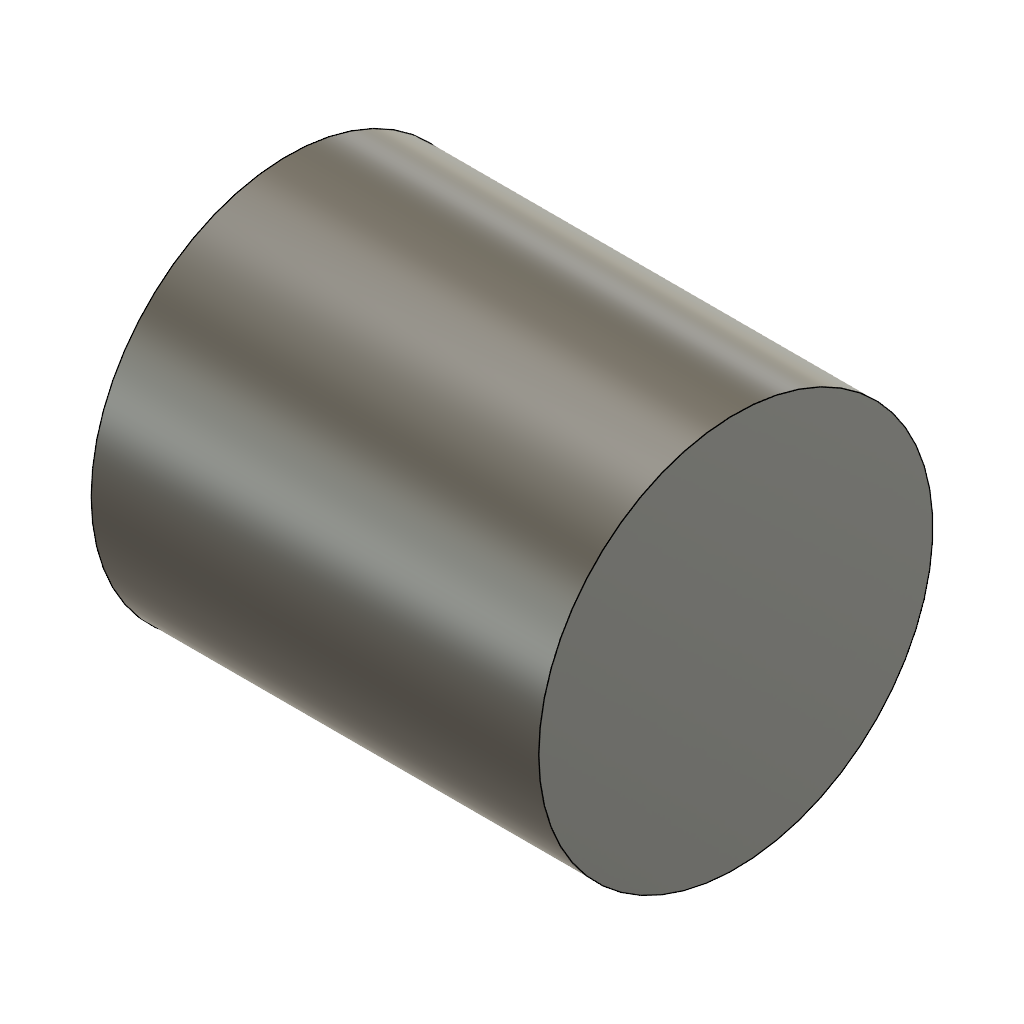
holdout_f_edit_second (Autodesk Fusion 360 design; units mm, degrees)
part number: 2026-11-27-17-36-56-333
Autodesk Fusion 360 part; units mm, degrees
sketch "CircularProfile" plane through (0, 0, 0) normal (1, 0, 0) x (0, 0, -1)
  circle A0 centre (41, 23) radius 29
extrude "OffsetTwoSides" add sketch "CircularProfile" along normal blind 43.75 and the other way blind 22.125 from surface at 2.25
